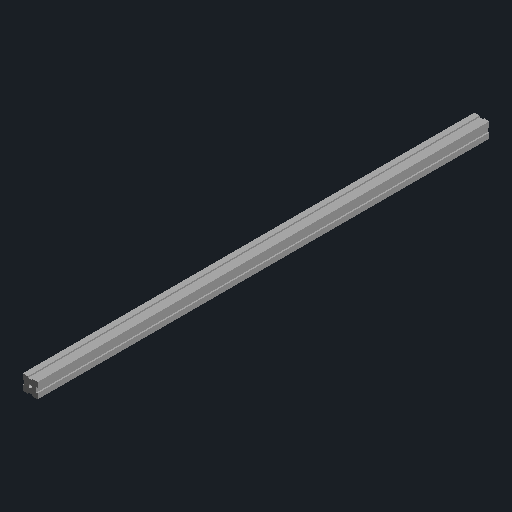
# Autodesk Inventor part: Perfil_2020_L600
Saved by Autodesk Inventor 2027.2 (Build 312334000, 334)
## iProperties
Part Number: Perfil_2020_L600
Material: Genérico
Document SubType Name: Modelado
Designer: Usuario
Appearance: Por defecto
Author: Usuario
Autodesk Inventor part; units mm, degrees
ref_plane "Plano YZ" through (0, 0, 0) normal (1, 0, 0) x (0, 1, 0)
ref_plane "Plano XZ" through (0, 0, 0) normal (0, 1, 0) x (-1, 0, 0)
ref_plane "Plano XY" through (0, 0, 0) normal (0, 0, 1) x (1, 0, 0)
sketch "Boceto1" plane through (0, 0, 0) normal (0, 0, 1) x (1, 0, 0)
  line L0 (-10, -10) -> (10, -10)
  line L1 (10, -10) -> (10, 10)
  line L2 (10, 10) -> (-10, 10)
  line L3 (-10, 10) -> (-10, -10)
  circle A0 centre (0, 0) radius 2.1
  line L4 (-3, 8.2) -> (3, 8.2)
  line L5 (3, 8.2) -> (3, 10)
  line L6 (3, 10) -> (-3, 10)
  line L7 (-3, 10) -> (-3, 8.2)
  line L8 (-3, -10) -> (3, -10)
  line L9 (3, -10) -> (3, -8.2)
  line L10 (3, -8.2) -> (-3, -8.2)
  line L11 (-3, -8.2) -> (-3, -10)
  line L12 (8.2, -3) -> (10, -3)
  line L13 (10, -3) -> (10, 3)
  line L14 (10, 3) -> (8.2, 3)
  line L15 (8.2, 3) -> (8.2, -3)
  line L16 (-10, -3) -> (-8.2, -3)
  line L17 (-8.2, -3) -> (-8.2, 3)
  line L18 (-8.2, 3) -> (-10, 3)
  line L19 (-10, 3) -> (-10, -3)
  constraints: 40 end point, 10 parallel, 5 horizontal, 5 perpendicular, 1 centre point
extrude "Extrusión1" add sketch "Boceto1" along normal blind 600 contours L3 L16 L17 L18 L2 L7 L4 L5 L1 L14 L15 L12 L0 L9 L10 L11
